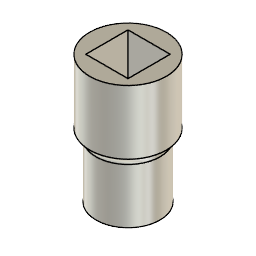
D shaft to square shaft adapter (Autodesk Fusion 360 design; units mm, degrees)
Autodesk Fusion 360 part; units mm, degrees
sketch "Sketch1" plane through (0, 0, 0) normal (0, 0, 1) x (1, 0, 0)
  circle A0 centre (0, 0) radius 2.5
  line L0 (0, -1.6) -> (0, 1.1) construction
  line L1 (-1.1619, 1.1) -> (1.1619, 1.1)
  arc A1 (-1.1619, 1.1) -> (1.1619, 1.1) centre (0, 0) ccw
  dimension "d1" = 3.2
  dimension "d2" = 5
  dimension "d11" = 2.7
  constraint coincident A0.centre A1.centre
  constraint concentric A0 A1
  constraint coincident L0.start A1
  constraint vertical L0
  constraint perpendicular L0 L1
  constraint coincident A0.centre L0
  constraint coincident L0.end L1
  measures "d1" diameter of A1
  measures "d2" diameter of A0
  measures "d11" distance of L0.start L0.end
extrude "Extrude1" add sketch "Sketch1" along normal blind 5
sketch "Sketch3" plane through (0, 0, 5) normal (0, 0, 1) x (-1, 0, 0)
  arc A0 (1.1619, -1.1) -> (-1.1619, -1.1) centre (0, 0) ccw
  line L0 (1.1619, -1.1) -> (-1.1619, -1.1)
  circle A1 centre (0, 0) radius 2.5
  line L1 (-1.651, -1.651) -> (1.651, -1.651)
  line L2 (1.651, -1.651) -> (1.651, 1.651)
  line L3 (1.651, 1.651) -> (-1.651, 1.651)
  line L4 (-1.651, 1.651) -> (-1.651, -1.651)
  line L5 (-1.651, -1.651) -> (1.651, 1.651) construction
  line L6 (1.651, -1.651) -> (-1.651, 1.651) construction
  circle A2 centre (0, 0) radius 3
  dimension "d12" = 3.302
  dimension "d13" = 3.302
  dimension "d14" = 6
  constraint horizontal L1
  constraint perpendicular L1 L2
  constraint parallel L1 L3
  constraint parallel L2 L4
  constraint coincident L5 A0.centre
  constraint coincident L6 A0.centre
  constraint coincident A0.centre A1.centre
  measures "d12" distance of L1.end L2.end
  measures "d13" distance of L1.start L1.end
  measures "d14" diameter of A2
extrude "Extrude2" add sketch "Sketch3" along normal blind 5 contours A1 | A2
fillet "Fillet1" radius 0.75 1 edges at (-2.3308, -0.904, 5)
